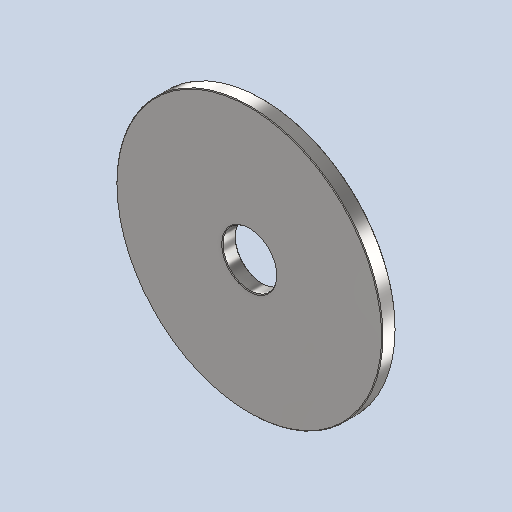
# Autodesk Inventor part: Anschweißlasche Scheibe
Saved by Autodesk Inventor 2026.2 (Build 302298010, 298A)
## iProperties
Created: 2026-07-28
Part Number: Anschweißlasche Scheibe
Material: Edelstahl
Document SubType Name: Modeling
Designer: moest
Density: 8 g/cm^3
Appearance: Halbpoliert
Author: moest
Autodesk Inventor part; units mm, degrees
ref_plane "YZ Plane" through (0, 0, 0) normal (1, 0, 0) x (0, 1, 0)
ref_plane "XZ Plane" through (0, 0, 0) normal (0, 1, 0) x (-1, 0, 0)
ref_plane "XY Plane" through (0, 0, 0) normal (0, 0, 1) x (1, 0, 0)
sketch "Skizze1" plane through (0, 0, 0) normal (0, 1, 0) x (-1, 0, 0)
  circle A0 centre (0, 0) radius 19.75
  circle A1 centre (0, 0) radius 4
  dimension "d0" = 39.5
  dimension "d1" = 8
  constraints: 2 centre point, 2 coincident
  measures "d0" diameter of A0
  measures "d1" diameter of A1
extrude "Extrusion1" add sketch "Skizze1" along normal blind 2
chamfer "Fasen1" distance 0.1 angle 45 2 edges at (19.75, 0, 0) (19.75, 2, 0)
chamfer "Fasen2" distance 0.1 angle 45 2 edges at (4, 0, 0) (4, 2, 0)
